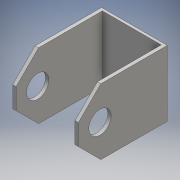
# Autodesk Inventor part: Tapak Roda
Saved by Autodesk Inventor 2016 (Build 200138000, 138)
## iProperties
Created: 2019-04-30
Part Number: Tapak Roda
Material: Generic
Document SubType Name: Modeling
Designer: User
Density: 1 g/cm^3
Appearance: Default
Author: User
Autodesk Inventor part; units mm, degrees
ref_plane "YZ Plane" through (0, 0, 0) normal (1, 0, 0) x (0, 1, 0)
ref_plane "XZ Plane" through (0, 0, 0) normal (0, 1, 0) x (-1, 0, 0)
ref_plane "XY Plane" through (0, 0, 0) normal (0, 0, 1) x (1, 0, 0)
sketch "Sketch1" plane through (0, 0, 0) normal (0, 1, 0) x (-1, 0, 0)
  line L0 (0, 0) -> (0, -38.1)
  line L1 (0, -38.1) -> (38.1, -38.1)
  line L2 (38.1, -38.1) -> (38.1, 0)
  line L3 (38.1, 0) -> (0, 0)
  dimension "d0" = 38.1
  dimension "d1" = 38.1
  constraints: 8 end point, 2 parallel, 1 perpendicular, 1 vertical
  measures "d0" distance of L0.start L0.end
  measures "d1" distance of L1.end L0.end
extrude "Extrusion1" add sketch "Sketch1" along normal blind 1.5
sketch "Sketch2" plane through (0, 1.5, 0) normal (0, 1, 0) x (1, 0, 0)
  line L0 (0, 0) -> (0, 38.1) projected
  line L1 (0, 19.05) -> (-19.05, 19.05)
  line L2 (-38.1, 38.1) -> (-38.1, 0) projected
  circle A0 centre (-19.05, 19.05) radius 6.5
  dimension "d4" = 19.05
  dimension "d5" = 13
  constraints: 2 end point, 1 centre point, 1 coincident, 1 midpoint, 1 perpendicular
  measures "d4" distance of L1.start L1.end
  measures "d5" diameter of A0
extrude "Extrusion2" cut sketch "Sketch2" against normal blind 0.5
sketch "Sketch3" plane through (0, 0, 0) normal (0, -1, 0) x (1, 0, 0)
  line L0 (0, 0) -> (0, -38.1) projected
  line L1 (0, 0) -> (0, -38.1)
  line L2 (0, -38.1) -> (-2, -38.1)
  line L3 (-2, -38.1) -> (-2, 0)
  line L4 (-2, 0) -> (0, 0)
  dimension "d8" = 38.1
  dimension "d9" = 2
  constraints: 8 end point, 2 parallel, 1 perpendicular, 1 point on line
  measures "d8" distance of L0.start L1.end
  measures "d9" distance of L1.end L2.end
extrude "Extrusion3" add sketch "Sketch3" along normal blind 50
sketch "Sketch4" plane through (0, 1.5, 0) normal (1, 0, 0) x (0, 0, -1)
  line L0 (38.1, -1.5) -> (0, -1.5) projected
  line L1 (19.05, -1.5) -> (19.05, -39)
  circle A0 centre (19.05, -39) radius 6.5
  dimension "d12" = 37.5
  dimension "d13" = 13
  constraints: 2 end point, 1 centre point, 1 coincident, 1 midpoint, 1 vertical
  measures "d12" distance of L1.start L1.end
  measures "d13" diameter of A0
extrude "Extrusion4" cut sketch "Sketch4" against normal blind 2
chamfer "Chamfer1" distance 13 angle 45 2 edges at (-1, -50, 0) (-1, -50, -38.1)
pattern_linear "Rectangular Pattern1" count 2 spacing 36.1 along (-1, 0, 0) of "Extrusion3", "Extrusion4", "Chamfer1"
body "Solid1"
